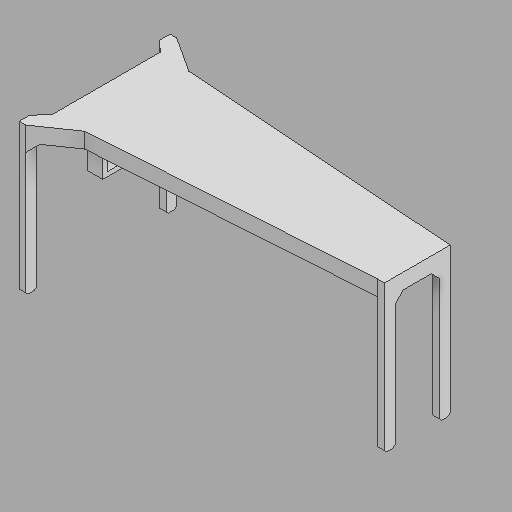
# Autodesk Inventor part: Techo parqueo
Saved by Autodesk Inventor 2027.1 (Build 311270010, 270A)
## iProperties
Created: 2026-11-08
Part Number: Techo parqueo
Material: Generic
Document SubType Name: Modeling
Designer: migue
Density: 1 g/cm^3
Appearance: Default
Author: migue
Autodesk Inventor part; units mm, degrees
ref_plane "YZ Plane" through (0, 0, 0) normal (1, 0, 0) x (0, 1, 0)
ref_plane "XZ Plane" through (0, 0, 0) normal (0, 1, 0) x (-1, 0, 0)
ref_plane "XY Plane" through (0, 0, 0) normal (0, 0, 1) x (1, 0, 0)
sketch "Sketch1" plane through (0, 0, 0) normal (0, 1, 0) x (-1, 0, 0)
  line L0 (5.1343, -14.9) -> (8.1343, -14.9)
  line L1 (8.1343, -14.9) -> (8.1343, -10.1)
  line L2 (8.1343, -10.1) -> (5.1343, -10.1)
  line L3 (5.1343, -10.1) -> (5.1343, -14.9)
  line L4 (5.1343, 14.9) -> (8.1343, 14.9)
  line L5 (8.1343, 14.9) -> (8.1343, 10.1)
  line L6 (8.1343, 10.1) -> (5.1343, 10.1)
  line L7 (5.1343, 10.1) -> (5.1343, 14.9)
  line L8 (-24.0792, -109.0435) -> (-27.0792, -109.0435)
  line L9 (148.6683, 34.2554) -> (151.6683, 34.2554)
  line L10 (151.6683, 34.2554) -> (151.6683, 29.4554)
  line L11 (151.6683, 29.4554) -> (148.6683, 29.4554)
  line L12 (148.6683, 29.4554) -> (148.6683, 34.2554)
  line L13 (0, 0) -> (153, 0) construction
  line L14 (153, -45) -> (153, 45) construction
  line L15 (151.6683, 34.2554) -> (148.6683, 29.4554) construction
  line L16 (148.6683, 34.2554) -> (151.6683, 29.4554) construction
  line L17 (8.1343, 14.9) -> (5.1343, 10.1) construction
  line L18 (5.1343, 14.9) -> (8.1343, 10.1) construction
  line L19 (8.1343, -10.1) -> (5.1343, -14.9) construction
  line L20 (8.1343, -14.9) -> (5.1343, -10.1) construction
  line L21 (151.6683, -29.4554) -> (148.6683, -29.4554)
  line L22 (148.6683, -29.4554) -> (148.6683, -34.2554)
  line L23 (148.6683, -34.2554) -> (151.6683, -34.2554)
  line L24 (151.6683, -34.2554) -> (148.6683, -29.4554) construction
  line L25 (148.6683, -34.2554) -> (151.6683, -29.4554) construction
  line L26 (151.6683, -34.2554) -> (151.6683, -29.4554)
  point P0 (6.6343, 10.1)
  point P1 (6.6343, -10.1)
  point P2 (150.1683, 31.8554)
  point P3 (6.6343, 12.5)
  point P4 (6.6343, 12.5)
  point P5 (6.6343, -12.5)
  point P6 (150.1683, -31.8554)
  dimension "d14" = 3
  dimension "d15" = 4.8
  dimension "d16" = 4.8
  dimension "d17" = 4.8
  dimension "d18" = 31.8554
  dimension "d19" = 12.5
  dimension "d20" = 12.5
  dimension "d21" = 140.5341
  dimension "d23" = 3
  constraints: 54 end point, 7 midpoint, 6 parallel, 5 symmetric about line, 3 horizontal, 3 perpendicular, 2 point on line, 1 coincident, 1 other
  measures "d14" distance of L10.end L11.end
  measures "d15" distance of L9.end L10.end
  measures "d16" distance of L1.start L2.start
  measures "d17" distance of L5.start L6.start
  measures "d18" distance from line of L13 point (150.168, 31.855)
  measures "d19" distance from line of L13 point (6.634, 12.5)
  measures "d20" distance from line of L13 point (6.634, -12.5)
  measures "d21" horizontal distance of L5.start L11.end
  measures "d23" distance of L6.start L6.end
extrude "Extrusion1" add sketch "Sketch1" along normal blind 60
sketch "Sketch2" plane through (0, 60, 0) normal (0, 1, 0) x (1, 0, 0)
  line L0 (-148.6683, -29.4554) -> (-151.6683, -29.4554) projected
  line L1 (-151.6683, -29.4554) -> (-146.8226, -24.2736)
  line L2 (-146.8226, -24.2736) -> (-146.8226, 24.9239)
  line L3 (-146.8226, 24.9239) -> (-151.6683, 29.4554)
  line L4 (-148.6683, -29.4554) -> (-151.6683, -29.4554) projected
  line L5 (-148.6683, -29.4554) -> (-151.6683, -29.4554) projected
  line L6 (-148.6683, -29.4554) -> (-151.6683, -29.4554) projected
  line L7 (-148.6683, -34.2554) -> (-148.6683, -29.4554) projected
  line L8 (-148.6683, -34.2554) -> (-148.6683, -29.4554) projected
  line L9 (-148.6683, -34.2554) -> (-148.6683, -29.4554) projected
  line L10 (-151.6683, -29.4554) -> (-151.6683, -34.2554) projected
  line L11 (-151.6683, -34.2554) -> (-148.6683, -34.2554) projected
  line L12 (-148.6683, -29.4554) -> (-151.6683, -29.4554) projected
  line L13 (-151.6683, -29.4554) -> (-151.6683, -34.2554) projected
  line L14 (-151.6683, -34.2554) -> (-148.6683, -34.2554) projected
  line L15 (-148.6683, -34.2554) -> (-148.6683, -29.4554) projected
  line L16 (-151.6683, -29.4554) -> (-151.6683, -34.2554) projected
  line L17 (-151.6683, -29.4554) -> (-151.6683, -34.2554) projected
  line L18 (-151.6683, -34.2554) -> (-148.6683, -34.2554) projected
  line L19 (-151.6683, -34.2554) -> (-148.6683, -34.2554) projected
  line L20 (-148.6683, -34.2554) -> (-148.6683, -29.4554) projected
  line L21 (-151.6683, -29.4554) -> (-151.6683, -34.2554) projected
  line L22 (-148.6683, -29.4554) -> (-151.6683, -29.4554) projected
  line L23 (-148.6683, -34.2554) -> (-148.6683, -29.4554) projected
  line L24 (-151.6683, -34.2554) -> (-148.6683, -34.2554) projected
  line L25 (-151.6683, -29.4554) -> (-151.6683, -34.2554) projected
  line L26 (-151.6683, -34.2554) -> (-148.6683, -34.2554) projected
  line L27 (-151.6683, 29.4554) -> (-148.6683, 29.4554) projected
  line L28 (-148.6683, 29.4554) -> (-148.6683, 34.2554) projected
  line L29 (-151.6683, 34.2554) -> (-151.6683, 29.4554) projected
  line L30 (-148.6683, 34.2554) -> (-151.6683, 34.2554) projected
  line L31 (-148.6683, 34.2554) -> (-151.6683, 34.2554) projected
  line L32 (-148.6683, 29.4554) -> (-148.6683, 34.2554) projected
  line L33 (-151.6683, 29.4554) -> (-148.6683, 29.4554) projected
  line L34 (-151.6683, 34.2554) -> (-151.6683, 29.4554) projected
  line L35 (-151.6683, 29.4554) -> (-148.6683, 29.4554) projected
  line L36 (-151.6683, 29.4554) -> (-148.6683, 29.4554) projected
  line L37 (-151.6683, 29.4554) -> (-148.6683, 29.4554) projected
  line L38 (-148.6683, 34.2554) -> (-151.6683, 34.2554) projected
  line L39 (-148.6683, 34.2554) -> (-151.6683, 34.2554) projected
  line L40 (-151.6683, 34.2554) -> (-151.6683, 29.4554) projected
  line L41 (-151.6683, 29.4554) -> (-148.6683, 29.4554) projected
  line L42 (-148.6683, 29.4554) -> (-148.6683, 34.2554) projected
  line L43 (-151.6683, 34.2554) -> (-151.6683, 29.4554) projected
  line L44 (-151.6683, 34.2554) -> (-151.6683, 29.4554) projected
  line L45 (-148.6683, 34.2554) -> (-151.6683, 34.2554) projected
  line L46 (-148.6683, 34.2554) -> (-151.6683, 34.2554) projected
  line L47 (-148.6683, 29.4554) -> (-148.6683, 34.2554) projected
  line L48 (-148.6683, 29.4554) -> (-148.6683, 34.2554) projected
  line L49 (-148.6683, 29.4554) -> (-148.6683, 34.2554) projected
  line L50 (-5.1343, -10.1) -> (-8.1343, -10.1) projected
  line L51 (-5.1343, -10.1) -> (-8.1343, -10.1) projected
  line L52 (-5.1343, -10.1) -> (-8.1343, -10.1) projected
  line L53 (-5.1343, -10.1) -> (-8.1343, -10.1) projected
  line L54 (-8.1343, -10.1) -> (-8.1343, -14.9) projected
  line L55 (-8.1343, -10.1) -> (-8.1343, -14.9) projected
  line L56 (-8.1343, -10.1) -> (-8.1343, -14.9) projected
  line L57 (-8.1343, -14.9) -> (-5.1343, -14.9) projected
  line L58 (-8.1343, -14.9) -> (-5.1343, -14.9) projected
  line L59 (-8.1343, -14.9) -> (-5.1343, -14.9) projected
  line L60 (-8.1343, -10.1) -> (-8.1343, -14.9) projected
  line L61 (-5.1343, -10.1) -> (-8.1343, -10.1) projected
  line L62 (-5.1343, -14.9) -> (-5.1343, -10.1) projected
  line L63 (-8.1343, -14.9) -> (-5.1343, -14.9) projected
  line L64 (-5.1343, -14.9) -> (-5.1343, -10.1) projected
  line L65 (-5.1343, -10.1) -> (-8.1343, -10.1) projected
  line L66 (-8.1343, -10.1) -> (-8.1343, -14.9) projected
  line L67 (-8.1343, -14.9) -> (-5.1343, -14.9) projected
  line L68 (-8.1343, -14.9) -> (-5.1343, -14.9) projected
  line L69 (-5.1343, -14.9) -> (-5.1343, -10.1) projected
  line L70 (-5.1343, -14.9) -> (-5.1343, -10.1) projected
  line L71 (-5.1343, -14.9) -> (-5.1343, -10.1) projected
  line L72 (-5.1343, -14.9) -> (-5.1343, -10.1) projected
  line L73 (-8.1343, 10.1) -> (-5.1343, 10.1) projected
  line L74 (-8.1343, 10.1) -> (-5.1343, 10.1) projected
  line L75 (-8.1343, 10.1) -> (-5.1343, 10.1) projected
  line L76 (-8.1343, 10.1) -> (-5.1343, 10.1) projected
  line L77 (-5.1343, 14.9) -> (-8.1343, 14.9) projected
  line L78 (-5.1343, 10.1) -> (-5.1343, 14.9) projected
  line L79 (-5.1343, 10.1) -> (-5.1343, 14.9) projected
  line L80 (-8.1343, 10.1) -> (-5.1343, 10.1) projected
  line L81 (-8.1343, 14.9) -> (-8.1343, 10.1) projected
  line L82 (-5.1343, 14.9) -> (-8.1343, 14.9) projected
  line L83 (-5.1343, 10.1) -> (-5.1343, 14.9) projected
  line L84 (-5.1343, 10.1) -> (-5.1343, 14.9) projected
  line L85 (-5.1343, 14.9) -> (-8.1343, 14.9) projected
  line L86 (-8.1343, 14.9) -> (-8.1343, 10.1) projected
  line L87 (-8.1343, 10.1) -> (-5.1343, 10.1) projected
  line L88 (-5.1343, 14.9) -> (-8.1343, 14.9) projected
  line L89 (-5.1343, 14.9) -> (-8.1343, 14.9) projected
  line L90 (-5.1343, 10.1) -> (-5.1343, 14.9) projected
  line L91 (-5.1343, 10.1) -> (-5.1343, 14.9) projected
  line L92 (-8.1343, 14.9) -> (-8.1343, 10.1) projected
  line L93 (-8.1343, 14.9) -> (-8.1343, 10.1) projected
  line L94 (-8.1343, 14.9) -> (-8.1343, 10.1) projected
  line L95 (-5.1343, 14.9) -> (-8.1343, 14.9) projected
  line L96 (-8.1343, 14.9) -> (-8.1343, 10.1) projected
  line L97 (-151.6683, 34.2554) -> (-151.6683, 29.4554) projected
  line L98 (-8.1343, -10.1) -> (-8.1343, -14.9) projected
  line L99 (-146.8226, -24.2736) -> (-8.1343, -14.9)
  line L100 (-146.8226, 24.9239) -> (-5.1343, 14.9)
  line L101 (-5.1343, -14.9) -> (-5.1343, 14.9)
  line L102 (-148.6683, -34.2554) -> (-132.8604, -23.33)
  line L103 (-148.6683, 34.2554) -> (-132.8604, 23.9361)
  point P0 (0, 0)
  constraints: 16 end point, 2 perpendicular, 2 point on line, 1 vertical, 11 other
extrude "Extrusion2" add sketch "Sketch2" along normal blind 7
chamfer "Chamfer1" distance 3.75 angle 45 6 edges at (-6.6343, 60, 10.1) (-6.6343, 60, -10.1) (-148.6683, 60, -31.8554) (-150.1683, 60, -29.4554) (-148.6683, 60, 31.8554) (-150.1683, 60, 29.4554)
chamfer "Chamfer2" distance 1 angle 45 8 edges at (-6.6343, 0, 14.9) (-6.6343, 0, 10.1) (-6.6343, 0, -10.1) (-6.6343, 0, -14.9) (-150.1683, 0, -29.4554) (-150.1683, 0, -34.2554) (-150.1683, 0, 34.2554) (-150.1683, 0, 29.4554)
sketch "Sketch3" plane through (-146.8226, 60, -24.9239) normal (-1, 0, 0) x (0, 0, 1)
  line L0 (0, 7) -> (49.1975, 7) projected
  line L1 (18.0988, -2) -> (31.0988, -2)
  line L2 (31.0988, -2) -> (31.0988, -21)
  line L3 (31.0988, -21) -> (18.0988, -21)
  line L4 (18.0988, -21) -> (18.0988, -2)
  line L5 (18.0988, -2) -> (31.0988, -21) construction
  line L6 (31.0988, -2) -> (18.0988, -21) construction
  line L7 (16.0988, 0) -> (33.0988, 0)
  line L8 (33.0988, 0) -> (33.0988, -23)
  line L9 (16.0988, -23) -> (16.0988, 0)
  line L10 (0, 0) -> (49.1975, 0) projected
  line L11 (16.0988, -23) -> (33.0988, -23)
  point P0 (24.9239, -60)
  point P1 (24.5988, -11.5)
  point P2 (31.0988, 7)
  point P3 (18.0988, 7)
  point P4 (24.5988, 0)
  dimension "d34" = 13
  dimension "d35" = 19
  dimension "d36" = 2
  dimension "d37" = 2
  dimension "d40" = 2
  constraints: 20 end point, 4 midpoint, 3 parallel, 2 horizontal, 2 perpendicular, 1 other
  measures "d34" distance of L1.start L1.end
  measures "d35" distance of L1.end L2.end
  measures "d36" distance between parallel lines of L4 L9
  measures "d37" distance between parallel lines of L2 L8
  measures "d40" distance between parallel lines of L3 L11
extrude "Extrusion3" add sketch "Sketch3" against normal blind 7
body "Solid1"
